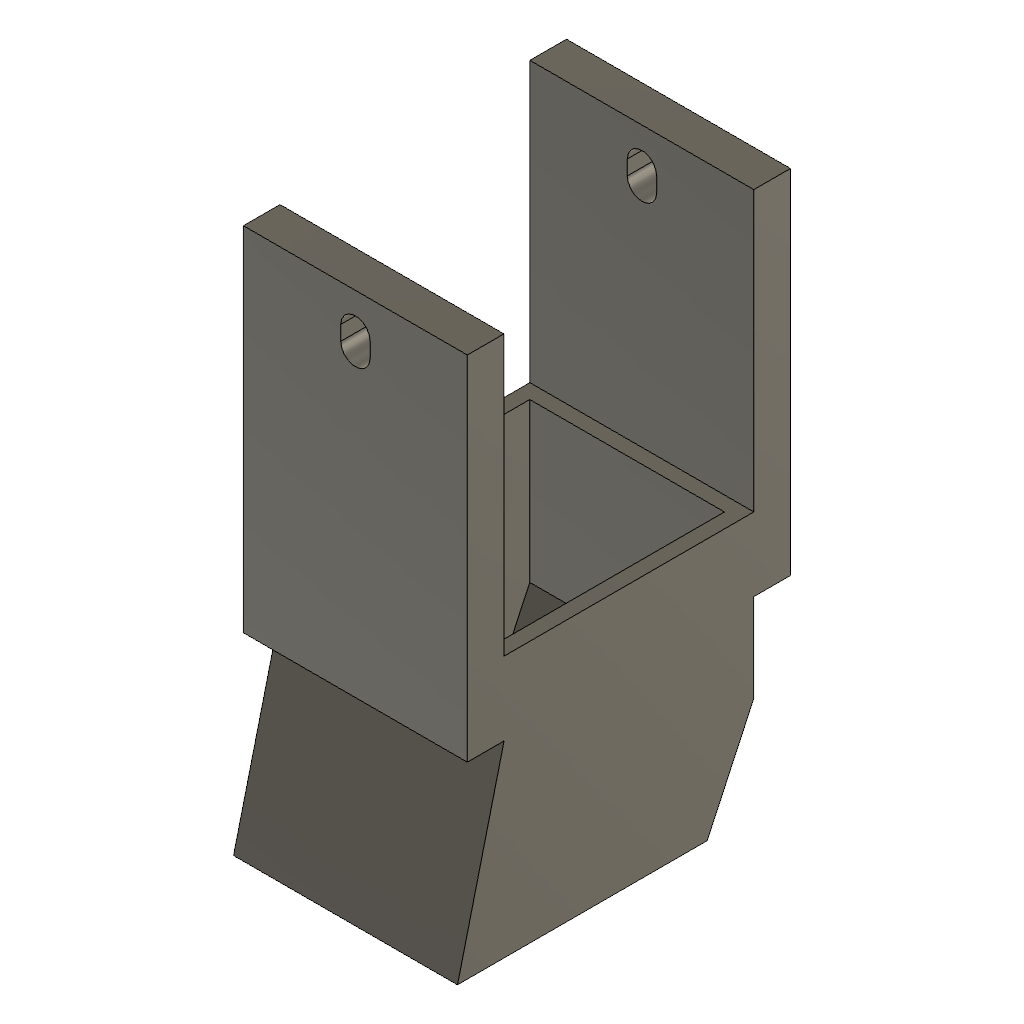
Chute - Blue 2x3 (Autodesk Fusion 360 design; units mm, degrees)
Autodesk Fusion 360 part; units mm, degrees
sketch "Sketch1" plane through (0, 0, 0) normal (0, 0, 1) x (1, 0, 0)
  line L0 (13.25, 15) -> (-13.25, 15)
  line L1 (-13.25, 15) -> (-13.25, -15)
  line L2 (-13.25, -15) -> (13.25, -15)
  line L3 (13.25, -15) -> (13.25, 15)
  line L4 (13.25, 15) -> (-13.25, -15) construction
  line L5 (-13.25, 15) -> (13.25, -15) construction
  line L6 (-15.25, -17) -> (15.25, -17)
  line L7 (15.25, -17) -> (15.25, 17)
  line L8 (15.25, 17) -> (-15.25, 17)
  line L9 (-15.25, 17) -> (-15.25, -17)
  line L10 (15.25, 22) -> (-15.25, 22)
  line L11 (-15.25, 22) -> (-15.25, -22)
  line L12 (-15.25, -22) -> (15.25, -22)
  line L13 (15.25, -22) -> (15.25, 22)
  line L14 (15.25, 22) -> (-15.25, -22) construction
  line L15 (-15.25, 22) -> (15.25, -22) construction
  dimension "d1" = 26.5
  dimension "d2" = 30
  dimension "d3" = 2
  dimension "d6" = 30.5
  dimension "d7" = 44
  constraint horizontal L0
  constraint perpendicular L0 L1
  constraint parallel L0 L2
  constraint parallel L1 L3
  constraint coincident L4 origin
  constraint coincident L5 origin
  constraint horizontal L10
  constraint perpendicular L10 L11
  constraint parallel L10 L12
  constraint parallel L11 L13
  constraint coincident L14 origin
  constraint coincident L15 origin
  measures "d1" distance of L1.end L2.end
  measures "d2" distance of L0.end L1.end
  measures "d6" distance of L11.end L12.end
  measures "d7" distance of L10.end L11.end
extrude "Extrude1" add sketch "Sketch1" along normal blind 10 contours L6 L7 L8 L9 L11 L13
extrude "Extrude2" add sketch "Sketch1" along normal blind 38 contours L6 L11 L12 L13 | L8 L10 L11 L13
sketch "Sketch2" plane through (0, 17, 0) normal (0, -1, 0) x (1, 0, 0)
  line L0 (-15.25, 10) -> (15.25, 10)
  line L1 (15.25, 10) -> (15.25, 38)
  line L2 (15.25, 38) -> (-15.25, 38)
  line L3 (-15.25, 38) -> (-15.25, 10)
  line L4 (-15.25, 38) -> (15, 38)
  line L5 (15, 38) -> (15, 33)
  line L6 (15, 33) -> (-15.25, 33)
  line L7 (-15.25, 33) -> (-15.25, 38)
  dimension "d10" = 5
  constraint horizontal L4
  constraint vertical L5
  constraint horizontal L6
  constraint vertical L7
  constraint coincident L2.end L3.start
  measures "d10" distance of L2.end L6.end
extrude "Extrude3" add 2 faces at (-5.0833, -18.6667, 38) (-5.0833, 18.6667, 38) along direction (0, 0, 1) blind 10
sketch "Sketch3" plane through (0, 22, 0) normal (0, 1, 0) x (-1, 0, 0)
  line L0 (-15.25, 0) -> (15.25, 0)
  line L1 (15.25, 0) -> (15.25, 48)
  line L2 (15.25, 48) -> (-15.25, 48)
  line L3 (-15.25, 48) -> (-15.25, 0)
  line L4 (-15.25, 48) -> (15.2032, 48)
  line L5 (15.2032, 48) -> (15.2032, 38)
  line L6 (15.2032, 38) -> (-15.25, 38)
  line L7 (-15.25, 38) -> (-15.25, 48)
  line L8 (-0.0234, 38) -> (-0.0234, 48)
  circle A0 centre (-0.0234, 43) radius 2
  circle A1 centre (-0.0234, 41) radius 2
  line L9 (-2.0234, 43) -> (-2.0234, 41)
  line L10 (1.9766, 41) -> (1.9766, 43)
  dimension "d13" = 10
  dimension "d14" = 4
  dimension "d30" = 4
  constraint horizontal L4
  constraint vertical L5
  constraint horizontal L6
  constraint vertical L7
  constraint coincident L2.end L3.start
  constraint midpoint L6 L8.start
  constraint midpoint L4 L8.end
  constraint midpoint L8 A0.centre
  constraint coincident L8 A1.centre
  constraint coincident A0 A1.centre
  constraint coincident A0 L9.start
  constraint coincident A1 L9.end
  constraint tangent A1 L9
  constraint parallel L8 L9
  constraint coincident A1 L10.start
  constraint coincident A0 L10.end
  constraint tangent A0 L10
  constraint parallel L8 L10
  measures "d13" distance of L2.end L6.end
  measures "d14" diameter of A0
  measures "d30" diameter of A1
extrude "Extrude4" cut sketch "Sketch3" against normal blind 57 contours L8 A0 A1 | L8 A0 A1 | L8 A0 A1 | L8 A0 A1 | L8 A0 A1 | L8 A0 A1 | A0 A1 L9 | A0 A1 L10
sketch "Sketch7" plane through (15.25, 0, 0) normal (1, 0, 0) x (0, 1, 0)
  line L0 (-22, 0) -> (22, 0)
  line L1 (22, 0) -> (22, 48)
  line L2 (22, 48) -> (17, 48)
  line L3 (17, 48) -> (17, 10)
  line L4 (17, 10) -> (-17, 10)
  line L5 (-17, 10) -> (-17, 48)
  line L6 (-17, 48) -> (-22, 48)
  line L7 (-22, 48) -> (-22, 0)
  line L8 (22, 0) -> (17, 0)
  line L9 (-22, 0) -> (-17, 0)
  line L10 (17, 0) -> (17, -12)
  line L11 (-17, 0) -> (-17, -12)
  line L12 (17, -12) -> (10.6607, -25.5946)
  line L13 (17, -12) -> (37, -12) construction
  line L14 (-17, -12) -> (-23.3393, -25.5946)
  line L15 (-17, -12) -> (3, -12) construction
  line L16 (-23.3393, -25.5946) -> (10.6607, -25.5946)
  line L17 (17, 0) -> (-17, 0)
  line L18 (-17, 0) -> (-23.3393, -25.5946)
  dimension "d31" = 5
  dimension "d32" = 5
  dimension "d33" = 12
  dimension "d34" = 12
  dimension "d35" = 115
  dimension "d36" = 15
  dimension "d37" = 115
  dimension "d38" = 15
  constraint coincident L0.end L1.start
  constraint perpendicular L1 L8
  constraint coincident L0.start L7.end
  constraint perpendicular L7 L9
  constraint perpendicular L8 L10
  constraint perpendicular L0 L11
  constraint horizontal L13
  constraint horizontal L15
  measures "d31" distance of L0.end L8.end
  measures "d32" distance of L0.start L9.end
  measures "d33" distance of L8.end L10.end
  measures "d34" distance of L9.end L11.end
  measures "d35" angle of L12 L13
  measures "d36" distance of L10.end L12.end
  measures "d37" angle of L14 L15
  measures "d38" distance of L11.end L14.end
extrude "Extrude6" add sketch "Sketch7" against normal blind 30.5 contours L0 L10 L11 L12 L14 L16 L17 | L11 L14 L18
shell "Shell2" thickness 2 removed faces 2 at (5.0833, -12.0059, -25.5946) at (4.4167, -5, 0)
